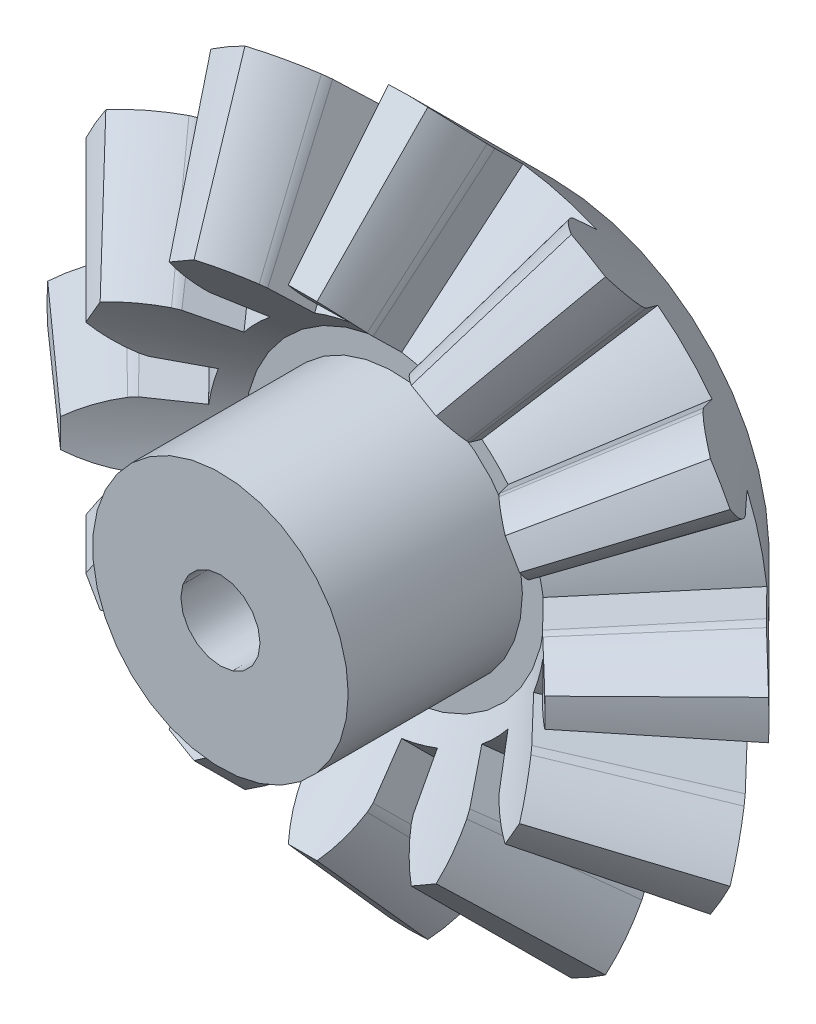
# Autodesk Inventor part: RayTest-Recovery-20260922-0555-1
Saved by Autodesk Inventor 2027 (Build 310192000, 192)
## iProperties
Part Number: RayTest-Recovery-20260922-0555-1
Created: 2000-11-23
Autodesk Inventor part; units mm, degrees
ref_plane "YZ Plane" through (0, 0, 0) normal (1, 0, 0) x (0, 1, 0)
ref_plane "XZ Plane" through (0, 0, 0) normal (0, 1, 0) x (-1, 0, 0)
ref_plane "Work Plane1" through (-10, 0, 0) normal (0, -0.7071068, 0.7071068) x (1, 0, 0)
sketch "Sketch3" plane through (0, 0, 0) normal (0, 0, 1) x (1, 0, 0)
  circle A0 centre (0, 0) radius 50.8
  line L0 (0, 0) -> (0, 50.8)
  dimension "d18" = 101.6
  constraints: 2 end point, 1 coincident, 1 vertical, 1 vertical alignment, 2 other
sketch "Sketch1" plane through (-10, 0, 0) normal (0, -0.7071068, 0.7071068) x (1, 0, 0)
  arc A0 (51.004067, 22.660149) -> (-31.004067, 22.660149) centre (10, 22.660149) ccw construction
  arc A1 (60.8, 22.660149) -> (-40.8, 22.660149) centre (10, 22.660149) ccw construction
  arc A2 (69.266667, 22.660149) -> (-49.266667, 22.660149) centre (10, 22.660149) ccw construction
  line L0 (10, 22.660149) -> (69.266667, 22.660149) construction
  line L1 (10, 22.660149) -> (-49.266667, 22.660149) construction
  line L2 (22.719304, 71.842049) -> (-25.890493, 84.413397) construction
  line L3 (22.719304, 71.842049) -> (-27.489771, 71.842049) construction
  arc A3 (59.1819, 22.660149) -> (-39.1819, 22.660149) centre (10, 22.660149) ccw construction
  arc A4 (6.839285, 81.842474) -> (3.369269, 73.025548) centre (27.281564, 68.705853) ccw
  arc A5 (3.369269, 73.025548) -> (3.279653, 71.380742) centre (9.952395, 71.842026) ccw
  line L4 (3.279653, 71.380742) -> (4.397094, 63.279614)
  line L5 (4.397094, 63.279614) -> (10, 22.660149) construction
  line L6 (10, 22.660149) -> (10, 81.926816) construction
  line L7 (3.369269, 73.025548) -> (10, 22.660149) construction
  arc A6 (16.630731, 73.025548) -> (13.160715, 81.842474) centre (-7.281564, 68.705853) ccw
  arc A7 (16.720347, 71.380742) -> (16.630731, 73.025548) centre (10.047605, 71.842026) ccw
  line L8 (16.720347, 71.380742) -> (15.602906, 63.279614)
  arc A8 (13.160715, 81.842474) -> (6.839285, 81.842474) centre (10, 22.660149) ccw
  arc A9 (15.602906, 63.279614) -> (4.397094, 63.279614) centre (10, 22.660149) ccw construction
  arc A10 (14.908761, 58.247262) -> (5.091239, 58.247262) centre (10, 22.660149) ccw
  line L9 (14.908761, 58.247262) -> (15.602906, 63.279614)
  line L10 (5.091239, 58.247262) -> (4.397094, 63.279614)
  point P0 (10, 71.842049)
  point P1 (10, 71.842049)
  point P2 (10, 63.664216)
  dimension "RC" = 41.00407
  dimension "PC" = 50.8
  dimension "AC" = 59.26667
  dimension "d4" = 14.5
  dimension "d5" = 24.29933
  dimension "d6" = 6.68867
  dimension "d7" = 7.5
  dimension "d49" = 5.08
  constraints: 32 point on circle, 22 end point, 11 centre point, 9 point on line, 7 coincident, 6 symmetric about line, 4 collinear, 2 concentric, 2 tangent, 1 equal length, 1 horizontal, 1 perpendicular, 1 vertical, 3 other
  measures "RC" radius of A0
  measures "PC" radius of A1
  measures "AC" radius of A2
  measures "d4" angle of L3 L2
  measures "d5" radius of A4
  measures "d6" radius of A5
  measures "d7" angle of L6 L7
  measures "d49" distance of L9.start L8.end
sketch "Sketch8" plane through (0, 0, 0) normal (1, 0, 0) x (0, 1, 0)
  line L0 (-44.041858, -44.041858) -> (86.451146, 86.451146)
  line L1 (0, -15.357909) -> (0, 92.147454)
  line L2 (24.157461, 60.078485) -> (0, 60.078485)
  line L3 (34.678485, 34.678485) -> (0, 34.678485)
  line L4 (27.056886, 62.977911) -> (24.157461, 60.078485)
  line L5 (45.017399, 45.017399) -> (27.056886, 62.977911)
  line L6 (39.970495, 75.891519) -> (57.931007, 57.931007)
  line L7 (27.056886, 62.977911) -> (24.157461, 60.078485)
  line L8 (27.056886, 62.977911) -> (39.970495, 75.891519)
  line L9 (39.970495, 75.891519) -> (40.86852, 76.789545)
  line L10 (40.86852, 76.789545) -> (58.829032, 58.829032)
  line L11 (27.146689, 63.067713) -> (45.107201, 45.107201)
  point P0 (0, 0)
  point P1 (16.023145, 16.023145)
  dimension "d38" = 25.4
  dimension "d59" = 4.10041
  dimension "d69" = 25.4
  dimension "d72" = 0.127
  dimension "d73" = 1.27
  constraints: 20 end point, 6 point on line, 3 parallel, 3 perpendicular, 2 collinear
  measures "d38" distance between parallel lines of L3 L2
  measures "d59" distance of L4.start L2.start
  measures "d69" distance of L9.end L10.end
  measures "d72" distance between parallel lines of L5 L11
  measures "d73" distance between parallel lines of L6 L10
extrude "Extrusion10" add sketch "Sketch1" along normal blind 27.94 draft -3.37229
pattern_circular "Circular Pattern3" count 12 over 360 about axis through (0, 0, -10) along (0, 0, 1) of "Extrusion10"
revolve "Revolution8" cut sketch "Sketch8" angle 360 about axis through (0, 0, -10) along (0, 0, 1) keep common part contours L3 L1 L2 L4 L5 L0 | L5 L8 L11 L0 | L11 L8 L6 L0 | L6 L9 L10 L0
revolve "Revolution9" add sketch "Sketch8" angle 360 about axis through (0, 0, -10) along (0, 0, 1) contours L3 L1 L2 L4 L5 L0 | L5 L8 L11 L0
sketch "Sketch11" plane through (0, 0, 60.078485) normal (0, 0, 1) x (1, 0, 0)
  circle A0 centre (0, 0) radius 24.157461
  circle A1 centre (0, 0) radius 6.35
  dimension "d74" = 12.7
  constraints: 1 centre point, 1 coincident
  measures "d74" diameter of A1
extrude "Extrusion11" cut sketch "Sketch11" along normal through all both and the other way through all contours A1
sketch "Sketch12" plane through (0, 0, 60.078485) normal (0, 0, 1) x (1, 0, 0)
  circle A0 centre (0, 0) radius 6.35
  circle A1 centre (0, 0) radius 24.157461
  circle A2 centre (0, 0) radius 20.502033
  dimension "d77" = 41.00407
  constraints: 1 centre point, 1 coincident
  measures "d77" diameter of A2
extrude "Extrusion12" add sketch "Sketch12" along normal blind 2.54 contours A2
sketch "Sketch13" plane through (0, 0, 34.678485) normal (0, 0, -1) x (-1, 0, 0)
  circle A0 centre (0, 0) radius 6.35
  circle A1 centre (0, 0) radius 34.678485
  circle A2 centre (0, 0) radius 20.502033
  dimension "d80" = 41.00407
  constraints: 1 centre point, 1 coincident
  measures "d80" diameter of A2
extrude "Extrusion13" add sketch "Sketch13" along normal blind 3.81 contours A2
sketch "Sketch14" plane through (0, 0, 62.618485) normal (0, 0, 1) x (1, 0, 0)
  circle A0 centre (0, 0) radius 6.35
  circle A1 centre (0, 0) radius 20.502033
extrude "Extrusion14" add sketch "Sketch14" along normal blind 25.4
thread "Thread1" size "1/2-13 UNC" class "2B" standard "ANSI Unified Screw Threads" full length
equation "\"d18\" = Dp"
equation "\"RC\" = 0.5 * Dr"
equation "\"PC\" = 0.5 * Dp"
equation "\"AC\" = 0.5 * Do"
equation "\"d4\" = Pangle"
equation "\"d7\" = 0.5 * t"
equation "\"d49\" = 0.2 * Thickness"
equation "\"d38\" = Thickness"
equation "\"d59\" = 0.1 * RC"
equation "\"d69\" = Thickness"
equation "\"d60\" = 1.1 * Thickness"
equation "\"d61\" = -ToothBevelAngle"
equation "\"d74\" = Shaft_Diameter"
equation "\"d75\" = 1.1 * Thickness"
equation "\"d77\" = RC"
equation "\"d78\" = 0.1 * Thickness"
equation "\"d80\" = RC"
equation "\"d81\" = 0.15 * Thickness"
equation "\"Dp\" = Pitch_Diameter"
equation "\"Pangle\" = Pressure_Angle"
equation "\"R\" = 72.898"
equation "\"r\" = 20.066"
equation "\"Thickness\" = 25.4"
equation "\"Shaft_Diameter\" = 12.7"
equation "\"Pitch_Diameter\" = 101.6"
equation "\"Pressure_Angle\" = 14.5deg"
equation "\"Dr\" = 82.008133"
equation "\"Do\" = 118.533333"
equation "\"t\" = 15deg"
equation "\"ToothBevelAngle\" = 3.372287deg"
body "Solid1"
